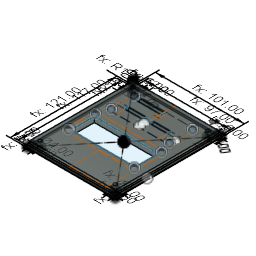
Temperature_Probe-2x-Alerter-LID v7 (Autodesk Fusion 360 design; units mm, degrees)
Autodesk Fusion 360 part; units mm, degrees
sketch "Sketch1" plane through (0, 0, 0) normal (0, 0, 1) x (1, 0, 0)
  line L0 (-48.5, -58.5) -> (48.5, -58.5)
  line L1 (48.5, -58.5) -> (48.5, 58.5)
  line L2 (48.5, 58.5) -> (-48.5, 58.5)
  line L3 (-48.5, 58.5) -> (-48.5, -58.5)
  line L4 (-48.5, -58.5) -> (48.5, 58.5) construction
  line L5 (48.5, -58.5) -> (-48.5, 58.5) construction
  line L6 (-49.5, 60.5) -> (49.5, 60.5)
  line L7 (50.5, 59.5) -> (50.5, -59.5)
  line L8 (49.5, -60.5) -> (-49.5, -60.5)
  line L9 (-50.5, -59.5) -> (-50.5, 59.5)
  line L10 (-50.5, 60.5) -> (50.5, -60.5) construction
  line L11 (50.5, 60.5) -> (-50.5, -60.5) construction
  arc A0 (-49.5, 60.5) -> (-50.5, 59.5) centre (-49.5, 59.5) ccw
  arc A1 (50.5, 59.5) -> (49.5, 60.5) centre (49.5, 59.5) ccw
  arc A2 (49.5, -60.5) -> (50.5, -59.5) centre (49.5, -59.5) ccw
  arc A3 (-50.5, -59.5) -> (-49.5, -60.5) centre (-49.5, -59.5) ccw
  line L12 (-48.5, 58.5) -> (-36.5, 58.5) construction
  line L13 (-36.5, 58.5) -> (-36.5, 46.5) construction
  line L14 (-36.5, 46.5) -> (-48.5, 46.5) construction
  line L15 (-48.5, 46.5) -> (-48.5, 58.5) construction
  line L16 (-48.5, 58.5) -> (-42.5, 58.5) construction
  line L17 (-42.5, 58.5) -> (-42.5, 52.5) construction
  line L18 (-42.5, 52.5) -> (-48.5, 52.5) construction
  line L19 (-48.5, 52.5) -> (-48.5, 58.5) construction
  circle A4 centre (-42.5, 52.5) radius 2
  line L20 (48.5, 58.5) -> (42.5, 58.5) construction
  line L21 (42.5, 58.5) -> (42.5, 52.5) construction
  line L22 (42.5, 52.5) -> (48.5, 52.5) construction
  line L23 (48.5, 52.5) -> (48.5, 58.5) construction
  circle A5 centre (42.5, 52.5) radius 2
  line L24 (48.5, -58.5) -> (42.5, -58.5) construction
  line L25 (42.5, -58.5) -> (42.5, -52.5) construction
  line L26 (42.5, -52.5) -> (48.5, -52.5) construction
  line L27 (48.5, -52.5) -> (48.5, -58.5) construction
  line L28 (-48.5, -58.5) -> (-42.5, -58.5) construction
  line L29 (-42.5, -58.5) -> (-42.5, -52.5) construction
  line L30 (-42.5, -52.5) -> (-48.5, -52.5) construction
  line L31 (-48.5, -52.5) -> (-48.5, -58.5) construction
  circle A6 centre (-42.5, -52.5) radius 2
  circle A7 centre (42.5, -52.5) radius 2
  line L32 (48.5, -22.5) -> (48.5, 0) construction
  dimension "d6" = 97
  dimension "d7" = 117
  dimension "d8" = 101
  dimension "d9" = 121
  dimension "d11" = 1
  dimension "d13" = 12
  dimension "d14" = 12
  dimension "d15" = 6
  dimension "d16" = 6
  dimension "d18" = 4
  dimension "d19" = 6
  dimension "d20" = 6
  dimension "d21" = 4
  dimension "d22" = 6
  dimension "d23" = 6
  dimension "d24" = 6
  dimension "d25" = 6
  dimension "d26" = 4
  dimension "d27" = 4
  constraint horizontal L0
  constraint perpendicular L0 L1
  constraint parallel L0 L2
  constraint parallel L1 L3
  constraint coincident L4 origin
  constraint coincident L5 origin
  constraint horizontal L6
  constraint perpendicular L6 L7
  constraint parallel L6 L8
  constraint parallel L7 L9
  constraint coincident L10 origin
  constraint coincident L11 origin
  constraint coincident L10.start L9
  constraint coincident L10.start L6
  constraint tangent L9 A0
  constraint tangent L6 A0
  constraint coincident L11.start L6
  constraint coincident L11.start L7
  constraint tangent L6 A1
  constraint tangent L7 A1
  constraint equal A0 A1
  constraint coincident L10.end L7
  constraint coincident L10.end L8
  constraint tangent L7 A2
  constraint tangent L8 A2
  constraint equal A0 A2
  constraint coincident L11.end L8
  constraint coincident L11.end L9
  constraint tangent L8 A3
  constraint tangent L9 A3
  constraint equal A0 A3
  constraint horizontal L12
  constraint vertical L13
  constraint horizontal L14
  constraint vertical L15
  constraint horizontal L16
  constraint vertical L17
  constraint horizontal L18
  constraint vertical L19
  constraint coincident L17.end L18.start
  constraint horizontal L20
  constraint vertical L21
  constraint horizontal L22
  constraint vertical L23
  constraint coincident L21.end L22.start
  constraint horizontal L24
  constraint vertical L25
  constraint horizontal L26
  constraint vertical L27
  constraint horizontal L28
  constraint vertical L29
  constraint horizontal L30
  constraint vertical L31
  constraint coincident L29.end L30.start
  constraint coincident L25.end L26.start
  constraint vertical L32
  constraint midpoint L1 L32.end
  measures "d6" distance of L1.end L2.end
  measures "d7" distance of L0.end L1.end
  measures "d8" distance of L10.end L11.end
  measures "d9" distance of L11.start L10.end
  measures "d11" radius of A0
  measures "d13" distance of L2.end L12.end
  measures "d14" distance of L2.end L14.end
  measures "d15" distance of L2.end L16.end
  measures "d16" distance of L2.end L18.end
  measures "d18" diameter of A4
  measures "d19" distance of L1.end L20.end
  measures "d20" distance of L1.end L22.end
  measures "d21" diameter of A5
  measures "d22" distance of L0.end L24.end
  measures "d23" distance of L0.end L26.end
  measures "d24" distance of L0.start L28.end
  measures "d25" distance of L0.start L30.end
  measures "d26" diameter of A6
  measures "d27" diameter of A7
extrude "Extrude1" add sketch "Sketch1" along normal blind 6 contours L0 L1 L2 L3 makes body 1
extrude "Extrude2" add sketch "Sketch1" along normal blind 3 contours L6 L7 L8 L9 A0 A1 A2 A3 bodies 1
extrude "Extrude3" add sketch "Sketch1" along normal blind 4 contours A4 | A5 | A6 | A7 bodies 1
hole "Hole1" at (42.5, -52.5, 0) at (-42.5, -52.5, 0) at (42.5, 52.5, 0) at (-42.5, 52.5, 0) direction (0, 0, 1) diameter 4 depth 10 tip angle 118 countersink diameter 6.6 countersink angle 90 bodies 1
sketch "Sketch2" plane through (0, 0, 6) normal (0, 0, 1) x (-1, 0, 0)
  circle A0 centre (42.5, -52.5) radius 2
  circle A1 centre (-42.5, -52.5) radius 2
  circle A2 centre (42.5, 52.5) radius 2
  circle A3 centre (-42.5, 52.5) radius 2
  line L0 (48.5, -58.5) -> (48.5, 58.5)
  line L1 (48.5, 58.5) -> (-48.5, 58.5)
  line L2 (-48.5, 58.5) -> (-48.5, -58.5)
  line L3 (-48.5, -58.5) -> (48.5, -58.5)
  line L4 (48.5, -58.5) -> (0, -58.5) construction
  line L5 (0, -58.5) -> (0, -46.5) construction
  line L6 (0, -46.5) -> (48.5, -46.5) construction
  line L7 (48.5, -46.5) -> (48.5, -58.5) construction
  line L8 (0, -46.5) -> (-35, -46.5) construction
  line L9 (-35, -46.5) -> (-35, -16.5) construction
  line L10 (-35, -16.5) -> (0, -16.5) construction
  line L11 (0, -16.5) -> (0, -46.5) construction
  line L12 (0, -46.5) -> (35, -46.5) construction
  line L13 (35, -46.5) -> (35, -16.5) construction
  line L14 (35, -16.5) -> (0, -16.5) construction
  line L15 (0, -16.5) -> (0, -46.5) construction
  line L16 (35, -46.5) -> (33, -46.5) construction
  line L17 (33, -46.5) -> (33, -44.5) construction
  line L18 (33, -44.5) -> (35, -44.5) construction
  line L19 (35, -44.5) -> (35, -46.5) construction
  line L20 (35, -16.5) -> (33, -16.5) construction
  line L21 (33, -16.5) -> (33, -18.5) construction
  line L22 (33, -18.5) -> (35, -18.5) construction
  line L23 (35, -18.5) -> (35, -16.5) construction
  line L24 (-35, -16.5) -> (-33, -16.5) construction
  line L25 (-33, -16.5) -> (-33, -18.5) construction
  line L26 (-33, -18.5) -> (-35, -18.5) construction
  line L27 (-35, -18.5) -> (-35, -16.5) construction
  line L28 (-35, -46.5) -> (-33, -46.5) construction
  line L29 (-33, -46.5) -> (-33, -44.5) construction
  line L30 (-33, -44.5) -> (-35, -44.5) construction
  line L31 (-35, -44.5) -> (-35, -46.5) construction
  circle A4 centre (33, -44.5) radius 1
  circle A5 centre (33, -44.5) radius 2.5
  circle A6 centre (-33, -44.5) radius 1
  circle A7 centre (-33, -44.5) radius 2.5
  circle A8 centre (-33, -18.5) radius 1
  circle A9 centre (-33, -18.5) radius 2.5
  circle A10 centre (33, -18.5) radius 1
  circle A11 centre (33, -18.5) radius 2.5
  line L32 (-35, -16.5) -> (-29, -16.5) construction
  line L33 (-29, -16.5) -> (-29, -17.5) construction
  line L34 (-29, -17.5) -> (-35, -17.5) construction
  line L35 (-35, -17.5) -> (-35, -16.5) construction
  line L36 (0, -17.5) -> (0, -22.5) construction
  line L37 (-35, -22.5) -> (-35, -17.5) construction
  line L38 (0, -46.5) -> (-3, -46.5) construction
  line L39 (-3, -46.5) -> (-3, -36.9) construction
  line L40 (-3, -36.9) -> (0, -36.9) construction
  line L41 (0, -36.9) -> (0, -46.5) construction
  line L42 (0, -46.5) -> (3, -46.5) construction
  line L43 (3, -46.5) -> (3, -36.9) construction
  line L44 (3, -36.9) -> (0, -36.9) construction
  line L45 (0, -36.9) -> (0, -46.5) construction
  line L46 (0, 60.5) -> (-40, 60.5) construction
  line L47 (-40, 60.5) -> (-40, 28.5) construction
  line L48 (-40, 28.5) -> (0, 28.5) construction
  line L49 (0, 28.5) -> (0, 60.5) construction
  line L50 (-40, 28.5) -> (40, 28.5) construction
  line L51 (40, 28.5) -> (40, -7.5) construction
  line L52 (40, -7.5) -> (-40, -7.5) construction
  line L53 (-40, -7.5) -> (-40, 28.5) construction
  line L54 (40, -7.5) -> (37.5, -7.5) construction
  line L55 (37.5, -7.5) -> (37.5, -5) construction
  line L56 (37.5, -5) -> (40, -5) construction
  line L57 (40, -5) -> (40, -7.5) construction
  line L58 (40, 28.5) -> (37.5, 28.5) construction
  line L59 (37.5, 28.5) -> (37.5, 26) construction
  line L60 (37.5, 26) -> (40, 26) construction
  line L61 (40, 26) -> (40, 28.5) construction
  line L62 (-40, 28.5) -> (-37.5, 28.5) construction
  line L63 (-37.5, 28.5) -> (-37.5, 26) construction
  line L64 (-37.5, 26) -> (-40, 26) construction
  line L65 (-40, 26) -> (-40, 28.5) construction
  line L66 (-40, -7.5) -> (-37.5, -7.5) construction
  line L67 (-37.5, -7.5) -> (-37.5, -5) construction
  line L68 (-37.5, -5) -> (-40, -5) construction
  line L69 (-40, -5) -> (-40, -7.5) construction
  circle A12 centre (-37.5, -5) radius 1
  circle A13 centre (-37.5, -5) radius 2.5
  circle A14 centre (-37.5, 26) radius 1
  circle A15 centre (-37.5, 26) radius 2.5
  circle A16 centre (37.5, 26) radius 1
  circle A17 centre (37.5, 26) radius 2.5
  circle A18 centre (37.5, -5) radius 1
  circle A19 centre (37.5, -5) radius 2.5
  line L70 (40, -7.5) -> (37, -7.5) construction
  line L71 (37, -7.5) -> (37, 28.5) construction
  line L72 (37, 28.5) -> (40, 28.5) construction
  line L73 (40, 28.5) -> (40, -7.5) construction
  line L74 (-40, -7.5) -> (-37, -7.5) construction
  line L75 (-37, -7.5) -> (-37, 28.5) construction
  line L76 (-37, 28.5) -> (-40, 28.5) construction
  line L77 (-40, 28.5) -> (-40, -7.5) construction
  line L78 (-40, -7.5) -> (40, -7.5) construction
  line L79 (40, -7.5) -> (40, -2) construction
  line L80 (40, -2) -> (-40, -2) construction
  line L81 (-40, -2) -> (-40, -7.5) construction
  line L82 (-40, 28.5) -> (40, 28.5) construction
  line L83 (40, 28.5) -> (40, 24.5) construction
  line L84 (40, 24.5) -> (-40, 24.5) construction
  line L85 (-40, 24.5) -> (-40, 28.5) construction
  line L86 (37, -2) -> (-37, -2)
  line L87 (-37, -2) -> (-37, 24.5)
  line L88 (-37, 24.5) -> (37, 24.5)
  line L89 (37, -2) -> (35.75, -2) construction
  line L90 (35.75, -2) -> (35.75, -1) construction
  line L91 (35.75, -1) -> (37, -1) construction
  line L92 (37, -1) -> (37, -2) construction
  line L93 (35.75, -2) -> (35.75, 24.5)
  line L94 (35, -46.5) -> (28, -46.5) construction
  line L95 (28, -46.5) -> (28, -41.5) construction
  line L96 (28, -41.5) -> (35, -41.5) construction
  line L97 (35, -41.5) -> (35, -46.5) construction
  line L98 (35, -46.5) -> (-0.25, -46.5) construction
  line L99 (-0.25, -46.5) -> (-0.25, -45.5) construction
  line L100 (-0.25, -45.5) -> (35, -45.5) construction
  line L101 (35, -45.5) -> (35, -46.5) construction
  line L102 (-0.25, -45.5) -> (28, -45.5)
  line L103 (28, -45.5) -> (28, -41.5)
  line L104 (28, -41.5) -> (-0.25, -41.5)
  line L105 (-0.25, -41.5) -> (-0.25, -45.5)
  line L106 (35, -16.5) -> (25.7, -16.5) construction
  line L107 (25.7, -16.5) -> (25.7, -26.5) construction
  line L108 (25.7, -26.5) -> (35, -26.5) construction
  line L109 (35, -26.5) -> (35, -16.5) construction
  line L110 (35, -16.5) -> (5.25, -16.5) construction
  line L111 (5.25, -16.5) -> (5.25, -30.5) construction
  line L112 (5.25, -30.5) -> (35, -30.5) construction
  line L113 (35, -30.5) -> (35, -16.5) construction
  line L114 (25.7, -26.5) -> (5.25, -26.5)
  line L115 (5.25, -26.5) -> (5.25, -30.5)
  line L116 (5.25, -30.5) -> (25.7, -30.5)
  line L117 (25.7, -30.5) -> (25.7, -26.5)
  line L118 (-35, -16.5) -> (-22.5, -16.5) construction
  line L119 (-22.5, -16.5) -> (-22.5, -26.5) construction
  line L120 (-22.5, -26.5) -> (-35, -26.5) construction
  line L121 (-35, -26.5) -> (-35, -16.5) construction
  line L122 (-35, -16.5) -> (-2, -16.5) construction
  line L123 (-2, -16.5) -> (-2, -30.5) construction
  line L124 (-2, -30.5) -> (-35, -30.5) construction
  line L125 (-35, -30.5) -> (-35, -16.5) construction
  line L126 (-2, -30.5) -> (-22.5, -30.5)
  line L127 (-22.5, -30.5) -> (-22.5, -26.5)
  line L128 (-22.5, -26.5) -> (-2, -26.5)
  line L129 (-2, -26.5) -> (-2, -30.5)
  dimension "d47" = 12
  dimension "d48" = 35
  dimension "d49" = 30
  dimension "d50" = 35
  dimension "d51" = 30
  dimension "d52" = 2
  dimension "d53" = 2
  dimension "d54" = 2
  dimension "d55" = 2
  dimension "d56" = 2
  dimension "d57" = 2
  dimension "d58" = 2
  dimension "d59" = 2
  dimension "d60" = 2
  dimension "d61" = 5
  dimension "d62" = 2
  dimension "d63" = 5
  dimension "d64" = 2
  dimension "d65" = 5
  dimension "d66" = 2
  dimension "d67" = 5
  dimension "d68" = 6
  dimension "d69" = 1
  dimension "d70" = 35
  dimension "d71" = 5
  dimension "d72" = 3
  dimension "d73" = 9.6
  dimension "d74" = 3
  dimension "d75" = 9.6
  dimension "d80" = 40
  dimension "d81" = 32
  dimension "d82" = 80
  dimension "d83" = 36
  dimension "d84" = 2.5
  dimension "d85" = 2.5
  dimension "d86" = 2.5
  dimension "d87" = 2.5
  dimension "d88" = 2.5
  dimension "d89" = 2.5
  dimension "d90" = 2.5
  dimension "d91" = 2.5
  dimension "d92" = 2
  dimension "d93" = 5
  dimension "d94" = 2
  dimension "d95" = 5
  dimension "d96" = 2
  dimension "d97" = 5
  dimension "d98" = 2
  dimension "d99" = 5
  dimension "d100" = 3
  dimension "d101" = 36
  dimension "d102" = 3
  dimension "d103" = 36
  dimension "d104" = 80
  dimension "d105" = 5.5
  dimension "d106" = 80
  dimension "d107" = 4
  dimension "d122" = 1.25
  dimension "d123" = 1
  dimension "d124" = 7
  dimension "d125" = 5
  dimension "d126" = 35.25
  dimension "d127" = 1
  dimension "d128" = 9.3
  dimension "d129" = 10
  dimension "d130" = 29.75
  dimension "d131" = 14
  dimension "d132" = 12.5
  dimension "d133" = 10
  dimension "d134" = 33
  dimension "d135" = 14
  constraint horizontal L4
  constraint vertical L5
  constraint horizontal L6
  constraint vertical L7
  constraint coincident L0.start L3.end
  constraint horizontal L8
  constraint vertical L9
  constraint horizontal L10
  constraint vertical L11
  constraint horizontal L12
  constraint vertical L13
  constraint horizontal L14
  constraint vertical L15
  constraint horizontal L16
  constraint vertical L17
  constraint horizontal L18
  constraint vertical L19
  constraint horizontal L20
  constraint vertical L21
  constraint horizontal L22
  constraint vertical L23
  constraint horizontal L24
  constraint vertical L25
  constraint horizontal L26
  constraint vertical L27
  constraint horizontal L28
  constraint vertical L29
  constraint horizontal L30
  constraint vertical L31
  constraint coincident L17.end L18.start
  constraint concentric A4 A5
  constraint coincident L29.end L30.start
  constraint concentric A6 A7
  constraint coincident L25.end L26.start
  constraint concentric A8 A9
  constraint coincident L21.end L22.start
  constraint concentric A10 A11
  constraint horizontal L32
  constraint vertical L33
  constraint horizontal L34
  constraint vertical L35
  constraint vertical L36
  constraint vertical L37
  constraint horizontal L38
  constraint vertical L39
  constraint horizontal L40
  constraint vertical L41
  constraint horizontal L42
  constraint vertical L43
  constraint horizontal L44
  constraint vertical L45
  constraint horizontal L46
  constraint vertical L47
  constraint horizontal L48
  constraint vertical L49
  constraint horizontal L50
  constraint vertical L51
  constraint horizontal L52
  constraint vertical L53
  constraint horizontal L54
  constraint vertical L55
  constraint horizontal L56
  constraint vertical L57
  constraint horizontal L58
  constraint vertical L59
  constraint horizontal L60
  constraint vertical L61
  constraint horizontal L62
  constraint vertical L63
  constraint horizontal L64
  constraint vertical L65
  constraint horizontal L66
  constraint vertical L67
  constraint horizontal L68
  constraint vertical L69
  constraint coincident L67.end L68.start
  constraint concentric A12 A13
  constraint coincident L63.end L64.start
  constraint concentric A14 A15
  constraint coincident L59.end L60.start
  constraint concentric A16 A17
  constraint coincident L55.end L56.start
  constraint concentric A18 A19
  constraint horizontal L70
  constraint vertical L71
  constraint horizontal L72
  constraint vertical L73
  constraint horizontal L74
  constraint vertical L75
  constraint horizontal L76
  constraint vertical L77
  constraint horizontal L78
  constraint vertical L79
  constraint horizontal L80
  constraint vertical L81
  constraint horizontal L82
  constraint vertical L83
  constraint horizontal L84
  constraint vertical L85
  constraint horizontal L86
  constraint vertical L87
  constraint horizontal L88
  constraint coincident L75 L87.end
  constraint coincident L84 L87.end
  constraint coincident L71 L86.start
  constraint coincident L80 L86.start
  constraint horizontal L89
  constraint vertical L90
  constraint horizontal L91
  constraint vertical L92
  constraint vertical L93
  constraint coincident L84 L93.end
  constraint horizontal L94
  constraint vertical L95
  constraint horizontal L96
  constraint vertical L97
  constraint horizontal L98
  constraint vertical L99
  constraint horizontal L100
  constraint vertical L101
  constraint horizontal L102
  constraint vertical L103
  constraint horizontal L104
  constraint vertical L105
  constraint horizontal L106
  constraint vertical L107
  constraint horizontal L108
  constraint vertical L109
  constraint horizontal L110
  constraint vertical L111
  constraint horizontal L112
  constraint vertical L113
  constraint horizontal L114
  constraint vertical L115
  constraint horizontal L116
  constraint vertical L117
  constraint horizontal L118
  constraint vertical L119
  constraint horizontal L120
  constraint vertical L121
  constraint horizontal L122
  constraint vertical L123
  constraint horizontal L124
  constraint vertical L125
  constraint horizontal L126
  constraint vertical L127
  constraint horizontal L128
  constraint vertical L129
  measures "d47" distance of L0.start L6.end
  measures "d48" distance of L5.end L8.end
  measures "d49" distance of L5.end L10.end
  measures "d50" distance of L5.end L12.end
  measures "d51" distance of L5.end L10.end
  measures "d52" distance of L12.end L16.end
  measures "d53" distance of L12.end L18.end
  measures "d54" distance of L13.end L20.end
  measures "d55" distance of L13.end L22.end
  measures "d56" distance of L9.end L24.end
  measures "d57" distance of L9.end L26.end
  measures "d58" distance of L8.end L28.end
  measures "d59" distance of L8.end L30.end
  measures "d60" diameter of A4
  measures "d61" diameter of A5
  measures "d62" diameter of A6
  measures "d63" diameter of A7
  measures "d64" diameter of A8
  measures "d65" diameter of A9
  measures "d66" diameter of A10
  measures "d67" diameter of A11
  measures "d68" distance of L9.end L32.end
  measures "d69" distance of L9.end L34.end
  measures "d70" distance of L34.end L36.start
  measures "d71" distance of L34.end L37.start
  measures "d72" distance of L5.end L38.end
  measures "d73" distance of L5.end L40.end
  measures "d74" distance of L5.end L42.end
  measures "d75" distance of L5.end L40.end
  measures "d80" distance of L46.start L46.end
  measures "d81" distance of L46.start L48.end
  measures "d82" distance of L47.end L50.end
  measures "d83" distance of L47.end L52.end
  measures "d84" distance of L51.end L54.end
  measures "d85" distance of L51.end L56.end
  measures "d86" distance of L50.end L58.end
  measures "d87" distance of L50.end L60.end
  measures "d88" distance of L47.end L62.end
  measures "d89" distance of L47.end L64.end
  measures "d90" distance of L52.end L66.end
  measures "d91" distance of L52.end L68.end
  measures "d92" diameter of A12
  measures "d93" diameter of A13
  measures "d94" diameter of A14
  measures "d95" diameter of A15
  measures "d96" diameter of A16
  measures "d97" diameter of A17
  measures "d98" diameter of A18
  measures "d99" diameter of A19
  measures "d100" distance of L51.end L70.end
  measures "d101" distance of L51.end L50.end
  measures "d102" distance of L52.end L74.end
  measures "d103" distance of L52.end L47.end
  measures "d104" distance of L52.end L51.end
  measures "d105" distance of L52.end L80.end
  measures "d106" distance of L47.end L50.end
  measures "d107" distance of L47.end L84.end
  measures "d122" distance of L86.start L89.end
  measures "d123" distance of L86.start L91.end
  measures "d124" distance of L12.end L94.end
  measures "d125" distance of L12.end L96.end
  measures "d126" distance of L12.end L98.end
  measures "d127" distance of L12.end L100.end
  measures "d128" distance of L13.end L106.end
  measures "d129" distance of L13.end L108.end
  measures "d130" distance of L13.end L110.end
  measures "d131" distance of L13.end L112.end
  measures "d132" distance of L9.end L118.end
  measures "d133" distance of L9.end L120.end
  measures "d134" distance of L9.end L122.end
  measures "d135" distance of L9.end L124.end
extrude "Extrude5" cut sketch "Sketch2" against normal blind 6 contours A15 A17 L86 L87 L88 L93 bodies 1
extrude "Extrude7" cut sketch "Sketch2" against normal blind 6 contours A15 L87 L88 | A17 L88 L93 | A17 L88 L93 | A16 picked at (-36.8836, 23.8997) bodies 1
extrude "Extrude8" add sketch "Sketch2" along normal blind 1 contours A13 | A15 L87 L88 | A17 L88 L93 | A17 L88 L93 | A19 picked at (-36.4223, 24.7733) bodies 1
extrude "Extrude9" cut sketch "Sketch2" against normal blind 3 contours A12 | A14 | A16 | A18 bodies 1
extrude "Extrude10" cut sketch "Sketch2" against normal blind 3 contours A4 | A6 | A8 | A10 bodies 1
extrude "Extrude11" add sketch "Sketch2" along normal blind 2 separate body contours A5 | A7 | A9 | A11 makes body 2 at (30.5124, 44.7489, 6.6667) makes body 3 at (30.5124, 18.7489, 6.6667) makes body 4 at (-35.4876, 44.7489, 6.6667) makes body 5 at (-35.4876, 18.7489, 6.6667)
extrude "Extrude12" cut sketch "Sketch2" against normal blind 6 contours L102 L103 L104 L105 | L114 L115 L116 L117 | L126 L127 L128 L129 bodies 1
extrude "Extrude13" add 1 faces at (-39.4907, -26.1242, 7) along direction (0, 0, -1) blind 7 on bodies 1 bodies 1
extrude "Extrude14" add sketch "Sketch2" against normal blind 6 contours A16 bodies 1
extrude "Extrude15" cut sketch "Sketch2" against normal blind 4.5 contours A16 bodies 1
equation "length_outer = length_inner + lid_offset"
equation "length_inner = 115 mm + 2 mm"
equation "width_outer = width_inner + lid_offset"
equation "width_inner = 95 mm + 2 mm"
equation "lid_offset = 4 mm"
equation "d6 = width_inner"
equation "d7 = length_inner"
equation "d8 = width_outer"
equation "d9 = length_outer"
equation "outer_corner_fillet = 1 mm"
equation "d11 = outer_corner_fillet"
equation "lid_screw_hold_const_plane = 12 mm"
equation "d13 = lid_screw_hold_const_plane"
equation "d14 = lid_screw_hold_const_plane"
equation "d15 = lid_screw_hold_const_plane / 2"
equation "d16 = lid_screw_hold_const_plane / 2"
equation "hole_diameter = 4 mm"
equation "d18 = hole_diameter"
equation "d19 = lid_screw_hold_const_plane / 2"
equation "d20 = lid_screw_hold_const_plane / 2"
equation "d21 = hole_diameter"
equation "d22 = lid_screw_hold_const_plane / 2"
equation "d23 = lid_screw_hold_const_plane / 2"
equation "d24 = lid_screw_hold_const_plane / 2"
equation "d25 = lid_screw_hold_const_plane / 2"
equation "d26 = hole_diameter"
equation "d27 = hole_diameter"
equation "meter_length = 26.25 mm"
equation "meter_width = 45.25 mm"
equation "inner_thickness = 6 mm"
equation "outer_thickness = 3 mm"
equation "d36 = inner_thickness"
equation "d38 = outer_thickness"
equation "d40 = hole_diameter"
equation "d43 = hole_diameter"
equation "d110 = -inner_thickness"
